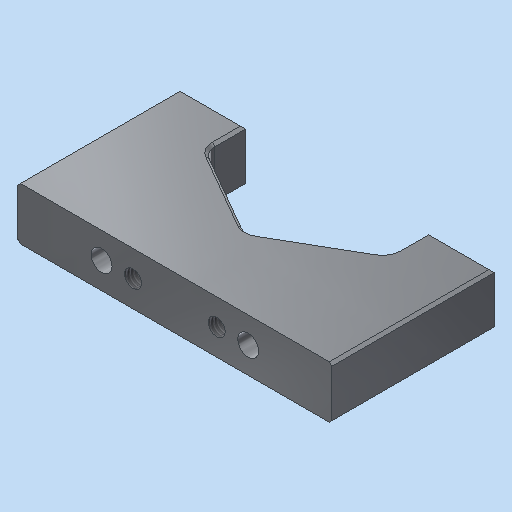
# Autodesk Inventor part: MM0948AN002_G01_120
Saved by Autodesk Inventor 2023.3 (Build 273359000, 359)
## iProperties
Created: 2017-02-07
Part Number: MM0948AN002_G01_120
Material: 3.3547 AlMg4,5Mn0,7 - AW 5083
Document SubType Name: Modeling
Designer: rat3an
Density: 2.66 g/cm^3
Appearance: Aluminium AnP
Description: =<RBPARTNOTITLE2>
Mass: 35.6808 g
Surface Area: 56.2968 cm^2
Volume: 13.4138 cm^3
RBMATERIAL: =<Material>
RBMATNO: =<Part Number>
RBPARTMADEOF: 10 x 31,2 x 60 (FM)
RBPARTNO: SIEHE MNR
RBPARTNOTITLE1: manufactured part
RBPARTNOTITLE2: Anfertigungsteil
AnP_Kommentar: farblos eloxiert
MaxAbmaße: 10 x 31,2 x 60 (FM)
AnP_Material_aktuell: =<Material>
AnP_Kommentar_aktuell: =<Comments>
RBDRAWINGMISSINGSPEC: --
AnP_Kategorie: 1
RBSURFACE: anodised colourless
RBSURFACE2: eloxiert farblos
AnP_Material: =<Material>
Author: rat3an
Keywords: =<RBPARTMADEOF>
Comments: =<RBSURFACE2>
Revision Number: 01
Autodesk Inventor part; units mm, degrees
ref_plane "YZ Plane" through (0, 0, 0) normal (1, 0, 0) x (0, 1, 0)
ref_plane "XZ Plane" through (0, 0, 0) normal (0, 1, 0) x (-1, 0, 0)
ref_plane "XY Plane" through (0, 0, 0) normal (0, 0, 1) x (1, 0, 0)
sketch "Skizze1" plane through (0, 0, 0) normal (0, 0, 1) x (1, 0, 0)
  line L0 (-30, 0) -> (30, 0)
  line L1 (30, 0) -> (30, 31)
  line L2 (30, 31) -> (-30, 31)
  line L3 (-30, 31) -> (-30, 0)
  line L4 (-42, 0) -> (42, 0) projected
  line L5 (0, 37.2) -> (0, -6.2) projected
  dimension "d0" = 31
  dimension "d1" = 60
  constraints: 8 end point, 2 parallel, 1 collinear, 1 horizontal, 1 perpendicular, 1 other
  measures "d0" distance between parallel lines of L0 L2
  measures "d1" distance between parallel lines of L1 L3
extrude "Extrusion1" add sketch "Skizze1" along normal mid plane 10
sketch "Skizze2" plane through (0, 0, 5) normal (0, 0, 1) x (1, 0, 0)
  line L0 (-30, 0) -> (30, 0) projected
  line L1 (30, 31) -> (-30, 31) projected
  line L2 (-30, 31) -> (-30, 0) projected
  line L3 (-17.5, 23.4272) -> (-2, 14.4783)
  line L4 (-2, 14.4783) -> (-2, 12.4783)
  line L5 (-2, 12.4783) -> (2, 12.4783)
  line L6 (2, 12.4783) -> (2, 14.4783)
  line L7 (2, 14.4783) -> (17.5, 23.4272)
  line L8 (0, 0) -> (0, 31)
  circle A0 centre (0, 23) radius 8.38
  line L9 (-17.5, 31) -> (17.5, 31)
  line L10 (30, 0) -> (30, 31) projected
  line L11 (-17.5, 31.38) -> (17.5, 31.38) construction
  line L12 (-2, 14.4783) -> (0, 13.3236)
  line L13 (2, 14.4783) -> (0, 13.3236)
  line L14 (-17.5, 23.4272) -> (-17.5, 31)
  line L15 (17.5, 23.4272) -> (17.5, 31)
  point P0 (0, 15.5)
  point P1 (-2.4949, 31)
  point P2 (2.4949, 31)
  point P3 (17.5, 31)
  point P4 (-17.5, 31)
  dimension "d6" = 16.76
  dimension "d8" = 2
  dimension "d9" = 2
  dimension "d10" = 4
  dimension "d55" = 35
  dimension "d68" = 120
  dimension "d124" = 35
  dimension "d128" = 23
  dimension "d129" = 0.38
  constraints: 24 end point, 6 perpendicular, 3 collinear, 3 midpoint, 2 tangent, 1 centre point, 1 horizontal alignment, 1 parallel, 1 point on line, 1 symmetric about line, 1 vertical, 1 vertical alignment, 2 other
  measures "d6" diameter of A0
  measures "d8" distance of L4.end L3.end
  measures "d9" distance of L5.end L6.end
  measures "d10" distance between parallel lines of L4 L6
  measures "d55" distance of L11.start L11.end
  measures "d68" angle of L7 L3
  measures "d124" distance of L7.end L3.start
  measures "d128" distance from line of L0 A0.centre
  measures "d129" distance between parallel lines of L1 L11
extrude "Extrusion2" cut sketch "Skizze2" against normal blind 15 contours L1 A0 L3 L14 | L12 L3 A0 L8 | L8 A0 L7 L13 | L1 L8 A0 | L15 L7 A0 L1 | L8 L1 A0
sketch "Skizze3" plane through (30, 31, 5) normal (0, 1, 0) x (1, 0, 0)
  line L0 (-30, 12) -> (-30, -2) projected
  line L1 (12, 5) -> (-72, 5) projected
  point P0 (-53.5, 5)
  point P1 (-6.5, 5)
  dimension "d65" = 47
  constraints: 1 horizontal alignment, 1 point on line, 1 symmetric about line
  measures "d65" distance of point (-6.5, 5) point (-53.5, 5)
hole "Bohrung2" at (-23.5, 31, 0) at (23.5, 31, 0) direction (0, -1, 0) diameter 3.242 depth 20 tip angle 118 thread size "M4x0.7" designation "M4" class "6H" standard "ISO Metric profile"
fillet "Rundung1" radius 3 3 edges at (0, 13.3236, 0) (-17.5, 23.4272, 0) (17.5, 23.4272, 0)
sketch "Skizze9" plane through (-30, 0, 5) normal (0, -1, 0) x (1, 0, 0)
  line L0 (30, 2) -> (30, -12) projected
  line L1 (60, -10) -> (0, -10) projected
  point P0 (30, -5)
  point P1 (22, -5)
  point P2 (38, -5)
  dimension "d106" = 16
  dimension "d107" = 5
  constraints: 1 symmetric about line
  measures "d106" distance of point (38, -5) point (22, -5)
  measures "d107" distance from line of L1 point (22, -5)
hole "Bohrung7" at (-8, 0, 0) at (8, 0, 0) direction (0, 1, 0) diameter 3.242 depth 11.8 tip angle 118 thread size "M4x0.7" designation "M4" class "6H" standard "ISO Metric profile"
sketch "Skizze10" plane through (-30, 0, 5) normal (0, -1, 0) x (1, 0, 0)
  line L0 (30, 2) -> (30, -12) projected
  circle A0 centre (22, -5) radius 1.621 projected
  circle A1 centre (38, -5) radius 1.621 projected
  line L1 (60, -10) -> (60, 0) projected
  line L2 (0, 0) -> (60, 0) projected
  line L3 (0, 0) -> (0, -10) projected
  line L4 (60, -10) -> (0, -10) projected
  point P0 (30, -5)
  point P1 (16, -5)
  point P2 (44, -5)
  dimension "d115" = 28
  constraints: 1 horizontal alignment, 1 symmetric about line
  measures "d115" distance of point (44, -5) point (16, -5)
hole "Bohrung8" at (-14, 0, 0) at (14, 0, 0) direction (0, 1, 0) diameter 4 depth 8 tip angle 118
chamfer "Fase6" distance 0.5 angle 45 22 edges at (-8.75, 18.3754, -5) (0, 13.7877, -5) (8.75, 18.3754, -5) (17.0981, 23.6593, -5) (17.5, 28.0796, -5) (-17.0981, 23.6593, -5) (-17.5, 28.0796, -5) (-8.75, 18.3754, 5) (-17.0981, 23.6593, 5) (-17.5, 28.0796, 5) (0, 13.7877, 5) (8.75, 18.3754, 5) (17.0981, 23.6593, 5) (17.5, 28.0796, 5) (23.75, 31, 5) (23.75, 31, -5) (-23.75, 31, 5) (-23.75, 31, -5) (30, 15.5, 5) (30, 15.5, -5) (-30, 15.5, 5) (-30, 15.5, -5)
